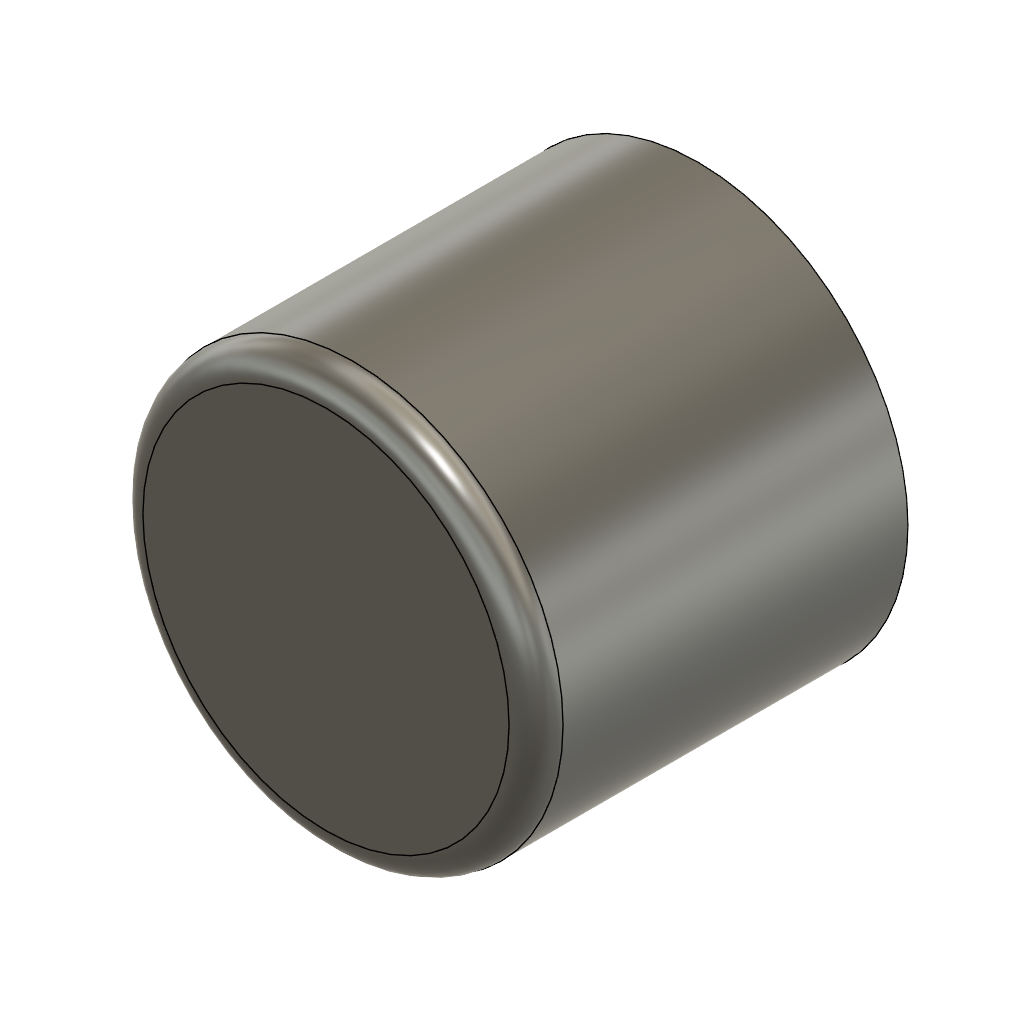
Native (Autodesk Fusion 360 design; units mm, degrees)
part number: 2026-11-25-22-47-38-950
Autodesk Fusion 360 part; units mm, degrees
sketch "Disc sketch" plane through (0, 0, 0) normal (0, 0, 1) x (1, 0, 0)
  circle A0 centre (0, 0) radius 17.9
extrude "Disc extrude" add sketch "Disc sketch" along normal blind 31.7
fillet "Rim round" radius 2.3 1 edges at (-16.6887, -6.4729, 31.7)
